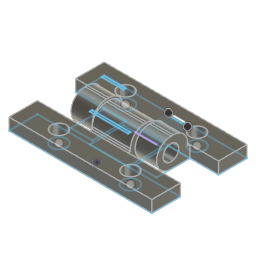
Hinge_30x6mm_M3 (Autodesk Fusion 360 design; units mm, degrees)
part number: 2026-04-11-15-28-25-390
Autodesk Fusion 360 part; units mm, degrees
sketch "Sketch1" plane through (0, 0, 0) normal (0, 0, 1) x (1, 0, 0)
  line L0 (15, 2.5) -> (-15, 2.5)
  line L1 (-15, 2.5) -> (-15, -3.5)
  line L2 (-15, -3.5) -> (15, -3.5)
  line L3 (15, -3.5) -> (15, 2.5)
  line L4 (-4, 2.5) -> (4, 2.5)
  line L5 (4, 2.5) -> (4, 9.5)
  line L6 (4, 9.5) -> (-4, 9.5)
  line L7 (-4, 9.5) -> (-4, 2.5)
  line L8 (4.5, 3.5) -> (9, 3.5)
  line L9 (9, 3.5) -> (9, 10.5)
  line L10 (9, 10.5) -> (4.5, 10.5)
  line L11 (4.5, 10.5) -> (4.5, 3.5)
  line L12 (-4.5, 3.5) -> (-9, 3.5)
  line L13 (-9, 3.5) -> (-9, 10.5)
  line L14 (-9, 10.5) -> (-4.5, 10.5)
  line L15 (-4.5, 10.5) -> (-4.5, 3.5)
  line L16 (15, 10.5) -> (-15, 10.5)
  line L17 (-15, 10.5) -> (-15, 16.5)
  line L18 (-15, 16.5) -> (15, 16.5)
  line L19 (15, 16.5) -> (15, 10.5)
  circle A0 centre (7.5, -0.5) radius 1.6
  circle A1 centre (-7.5, -0.5) radius 1.6
  circle A2 centre (7.5, 13.5) radius 1.6
  circle A3 centre (-7.5, 13.5) radius 1.6
  dimension "d32" = 3.2
  dimension "d33" = 3.2
  dimension "d34" = 3.2
  dimension "d35" = 3.2
  constraint horizontal L0
  constraint perpendicular L0 L1
  constraint parallel L0 L2
  constraint parallel L1 L3
  constraint horizontal L4
  constraint vertical L5
  constraint horizontal L6
  constraint vertical L7
  constraint coincident L0 L4.start
  constraint horizontal L8
  constraint vertical L9
  constraint horizontal L10
  constraint vertical L11
  constraint horizontal L12
  constraint vertical L13
  constraint horizontal L14
  constraint vertical L15
  constraint horizontal L16
  constraint vertical L17
  constraint horizontal L18
  constraint vertical L19
  measures "d32" diameter of A2
  measures "d33" diameter of A3
  measures "d34" diameter of A0
  measures "d35" diameter of A1
extrude "Extrude1" add sketch "Sketch1" along normal blind 2.5 contours L0 L1 L2 L3 L4 | L10 L14 L16 L17 L18 L19 makes body 1 at (-13.0333, 13.5, 0) makes body 2 at (-13.0333, -0.5, 0)
extrude "Extrude2" add sketch "Sketch1" along normal blind 6 separate body contours L0 L4 L5 L6 L7 | L8 L9 L10 L11 L16 | L12 L13 L14 L15 L16 makes body 3 at (4.5, 8.1667, 2) makes body 4 at (1.3333, 4.8333, 0) makes body 5 at (-4.5, 8.1667, 2)
sketch "Sketch2" plane through (9, 0, 0) normal (1, 0, 0) x (0, 1, 0)
  line L0 (3.5, 0) -> (10.5, 0)
  line L1 (10.5, 0) -> (10.5, 6)
  line L2 (10.5, 6) -> (3.5, 6)
  line L3 (3.5, 6) -> (3.5, 0)
  point P0 (6.5, 3)
hole "Hole1" at (9, 6.5, 3) direction (-1, 0, 0) diameter 3.3 depth 13 tip angle 180 bodies 3 4
sketch "Sketch3" plane through (-9, 0, 0) normal (-1, 0, 0) x (0, -1, 0)
  line L0 (-10.5, 0) -> (-3.5, 0)
  line L1 (-3.5, 0) -> (-3.5, 6)
  line L2 (-3.5, 6) -> (-10.5, 6)
  line L3 (-10.5, 6) -> (-10.5, 0)
  point P0 (-6.5, 3)
hole "Hole2" at (-9, 6.5, 3) direction (1, 0, 0) diameter 2.8 depth 4.5 tip angle 180 bodies 5
sketch "Sketch4" plane through (0, 0, 6) normal (0, 0, 1) x (-1, 0, 0)
  line L0 (-9, -3.5) -> (-9, -10.5)
  line L1 (-9, -10.5) -> (-4.5, -10.5)
  line L2 (-4.5, -10.5) -> (-4.5, -3.5)
  line L3 (9, -10.5) -> (4.5, -10.5)
  line L4 (4.5, -10.5) -> (4.5, -10)
  line L5 (4.5, -10) -> (9, -10)
  line L6 (9, -10) -> (9, -10.5)
  line L7 (-4.5, -10.5) -> (-9, -10.5)
  line L8 (-9, -10.5) -> (-9, -10)
  line L9 (-9, -10) -> (-4.5, -10)
  line L10 (-4.5, -10) -> (-4.5, -10.5)
  line L11 (4, -2.5) -> (-4, -2.5)
  line L12 (-4, -2.5) -> (-4, -3)
  line L13 (-4, -3) -> (4, -3)
  line L14 (4, -3) -> (4, -2.5)
  line L15 (-4.5, -3.5) -> (-9, -3.5)
  constraint horizontal L3
  constraint vertical L4
  constraint horizontal L5
  constraint vertical L6
  constraint horizontal L7
  constraint vertical L8
  constraint horizontal L9
  constraint vertical L10
  constraint coincident L0 L8.end
  constraint coincident L1.end L2.start
  constraint horizontal L11
  constraint vertical L12
  constraint horizontal L13
  constraint vertical L14
extrude "Extrude3" cut sketch "Sketch4" against normal blind 3.5 contours L0 L1 L2 L7 L8 L9 L10 | L3 L4 L5 L6 bodies 3 5
extrude "Extrude4" cut sketch "Sketch4" against normal blind 3.5 contours L11 L12 L13 L14 bodies 4
fillet "Fillet1" radius 3 9 edges at (6.75, 3.5, 6) (6.75, 3.5, 0) (6.75, 10, 6) (0, 9.5, 0) (0, 9.5, 6) (0, 3, 6) (-6.75, 3.5, 6) (-6.75, 3.5, 0) (-6.75, 10, 6) on bodies 3 4 5
